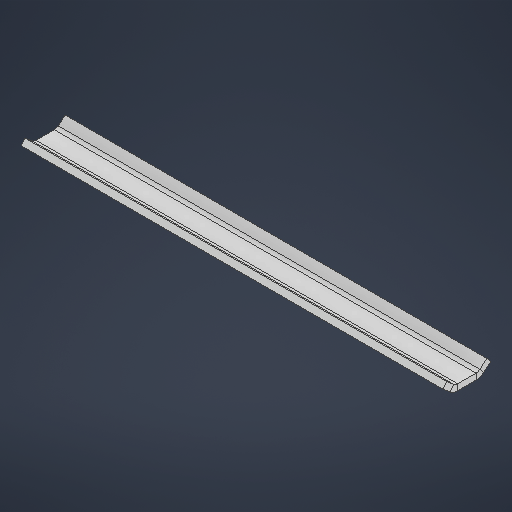
# Autodesk Inventor part: 中间本体
Saved by Autodesk Inventor 2025 (Build 290162000, 162)
## iProperties
Created: 2025-09-18
Part Number: 中间本体
Material: 常规
Document SubType Name: Sheet Metal
Designer: HZD
Density: 1 g/cm^3
Sheet Metal Rule: 默认_mm
Appearance: 默认
Author: HZD
Autodesk Inventor part; units mm, degrees
ref_plane "YZ Plane" through (0, 0, 0) normal (1, 0, 0) x (0, 1, 0)
ref_plane "XZ Plane" through (0, 0, 0) normal (0, 1, 0) x (-1, 0, 0)
ref_plane "XY Plane" through (0, 0, 0) normal (0, 0, 1) x (1, 0, 0)
sketch "草图1" plane through (0, 0, 0) normal (0, 1, 0) x (-1, 0, 0)
  line L0 (-35, -2.25) -> (35, -2.25)
  line L1 (35, -2.25) -> (35, 2.25)
  line L2 (35, 2.25) -> (-35, 2.25)
  line L3 (-35, 2.25) -> (-35, -2.25)
  line L4 (-35, -2.25) -> (35, 2.25) construction
  line L5 (35, -2.25) -> (-35, 2.25) construction
  point P0 (0, 0)
  dimension "d0" = 4.5
  dimension "d1" = 70
  measures "d0" distance of L0.end L1.end
  measures "d1" distance of L0.start L0.end
extrude "平板1" add sketch "草图1" along normal blind 1
sketch "草图2" plane through (35, 0.766, 1.6072) normal (0, -0.7660444, 0.6427876) x (1, 0, 0)
  line L0 (-70, 0) -> (0, 0)
  line L1 (0, 0) -> (0, 2.25)
  line L2 (0, 2.25) -> (-70, 2.25)
  line L3 (-70, 2.25) -> (-70, 0)
  constraints: 6 end point, 1 horizontal, 1 perpendicular, 1 vertical
edge flange "凸缘1" height 2.25 angle 40 thickness 1 bend radius 1 thickness toward (0, -0.7660444, 0.6427876) relief straight relief width 1 relief depth 0.5 edges at (0, 1, 2.25) wall of the first edge with corners at (-35, 0.766, 1.6072) (35, 0.766, 1.6072) (35, 2.2123, 3.3308) (-35, 2.2123, 3.3308)
bend "折弯1"
corner "拐角1"
sketch "草图3" plane through (-35, 0.766, -1.6072) normal (0, -0.7660444, -0.6427876) x (1, 0, 0)
  line L0 (70, 0) -> (0, 0)
  line L1 (0, 0) -> (0, -2.25)
  line L2 (0, -2.25) -> (70, -2.25)
  line L3 (70, -2.25) -> (70, 0)
  constraints: 6 end point, 1 horizontal, 1 perpendicular, 1 vertical
edge flange "凸缘2" height 2.25 angle 40 thickness 1 bend radius 1 thickness toward (0, -0.7660444, -0.6427876) relief straight relief width 1 relief depth 0.5 edges at (0, 1, -2.25) wall of the first edge with corners at (35, 0.766, -1.6072) (-35, 0.766, -1.6072) (-35, 2.2123, -3.3308) (35, 2.2123, -3.3308)
bend "折弯2"
corner "拐角2"
equation "\"d4\" = 厚度"
equation "\"d5\" = 折弯释压宽度"
equation "\"d6\" = 折弯释压深度"
equation "\"d7\" = 最小余量"
equation "\"d8\" = 过渡半径"
equation "\"d11\" = 折弯半径"
equation "\"d12\" = 拐角释压尺寸"
equation "\"d13\" = 间隙大小"
equation "\"d14\" = Jacobi半径尺寸"
equation "\"d15\" = 折弯释压宽度"
equation "\"d16\" = 折弯释压深度"
equation "\"d17\" = 最小余量"
equation "\"d18\" = 过渡半径"
equation "\"d21\" = 折弯半径"
equation "\"d22\" = 拐角释压尺寸"
equation "\"d23\" = 间隙大小"
equation "\"d24\" = Jacobi半径尺寸"
equation "\"折弯半径\" = 厚度"
equation "\"折弯释压宽度\" = 厚度"
equation "\"折弯释压深度\" = 0.5 * 厚度"
equation "\"拐角释压尺寸\" = 4 * 厚度"
equation "\"最小余量\" = 2 * 厚度"
equation "\"过渡半径\" = 折弯半径"
equation "\"Jacobi半径尺寸\" = 折弯半径"
equation "\"间隙大小\" = 厚度"
equation "\"厚度\" = 1"
